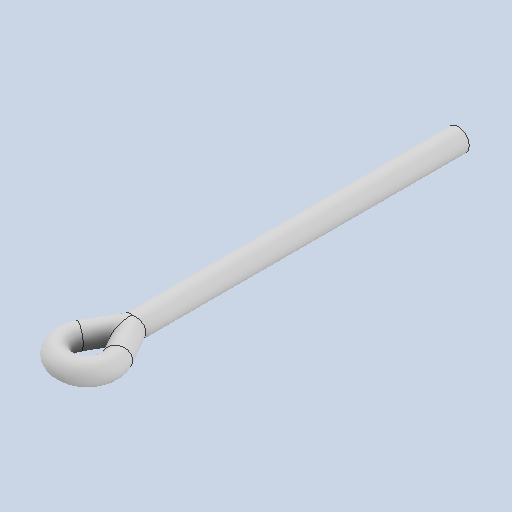
# Autodesk Inventor part: wire4
Saved by Autodesk Inventor 2026.1 (Build 301233020, 233B)
## iProperties
Created: 2025-12-01
Part Number: wire4
Material: Generico
Document SubType Name: Modeling
Designer: maxbu
Density: 1 g/cm^3
Appearance: Default
Author: maxbu
Autodesk Inventor part; units mm, degrees
ref_plane "YZ Plane" through (0, 0, 0) normal (1, 0, 0) x (0, 1, 0)
ref_plane "XZ Plane" through (0, 0, 0) normal (0, 1, 0) x (-1, 0, 0)
sketch "Schizzo1" plane through (0, 0, 0) normal (0, 1, 0) x (-1, 0, 0)
  arc A0 (1.299038, -2.25) -> (-1.299038, -2.25) centre (0, -1.5) ccw
  line L0 (0, -1.5) -> (0, 0) construction
  line L1 (0, -4.5) -> (1.299038, -2.25)
  line L2 (0, -4.5) -> (-1.299038, -2.25)
  line L3 (0, -1.5) -> (0, -4.5) construction
  dimension "d0" = 3
  dimension "d5" = 60
  constraints: 8 end point, 3 point on circle, 2 tangent, 2 vertical, 1 centre point
  measures "d0" diameter of A0
  measures "d5" angle of L2 L1
sketch "Schizzo2" plane through (0, 0, 0) normal (1, 0, 0) x (0, 1, 0)
  circle A0 centre (0, 0) radius 0.75
  dimension "d2" = 1.5
  constraints: 1 centre point, 1 coincident
  measures "d2" diameter of A0
sweep "Sweep1" add profiles "Schizzo2" path "Schizzo1" path curves A0 L2 L1
ref_plane "Piano di lavoro1" through (0, 0, -4.5) normal (0, 0, 1) x (1, 0, 0)
sketch "Schizzo3" plane through (0, 0, -4.5) normal (0, 0, 1) x (1, 0, 0)
  circle A0 centre (0, 0) radius 0.75
  dimension "d7" = 1.5
  constraints: 1 centre point, 1 coincident
  measures "d7" diameter of A0
extrude "Estrusione1" add sketch "Schizzo3" against normal blind 22
